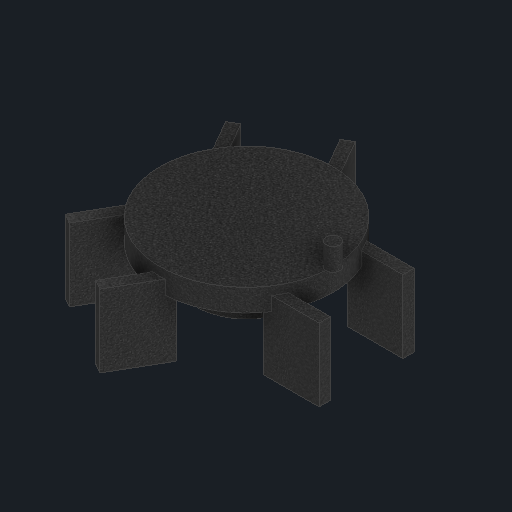
# Autodesk Inventor part: tripod_head
Saved by Autodesk Inventor 2027.1 (Build 311270010, 270A)
## iProperties
Created: 2026-11-03
Part Number: tripod_head
Material: Generic
Description: CG-5 tripod head (estimated)
Document SubType Name: Modeling
Designer: Claude (from photos)
Density: 1 g/cm^3
Appearance: Black Cast
Author: alexg
Autodesk Inventor part; units mm, degrees
ref_plane "YZ Plane" through (0, 0, 0) normal (1, 0, 0) x (0, 1, 0)
sketch "Tripod head plate sketch" plane through (0, 0, 0) normal (0, 1, 0) x (-1, 0, 0)
  circle A0 centre (0, 0) radius 62
  constraints: 1 centre point
extrude "Tripod head plate" add sketch "Tripod head plate sketch" against normal blind 16
ref_plane "Work Plane1" through (0, -16, 0) normal (0, 1, 0) x (-1, 0, 0)
sketch "Centre hub sketch" plane through (0, -16, 0) normal (0, 1, 0) x (-1, 0, 0)
  circle A0 centre (0, 0) radius 36
  constraints: 1 centre point
extrude "Centre hub" add sketch "Centre hub sketch" against normal blind 22
ref_plane "Work Plane2" through (0, -6, 0) normal (0, 1, 0) x (-1, 0, 0)
sketch "Leg hinge ears x3 sketch" plane through (0, -6, 0) normal (0, 1, 0) x (-1, 0, 0)
  line L0 (-46, 26) -> (-86, 26)
  line L1 (-86, 26) -> (-86, 34)
  line L2 (-86, 34) -> (-46, 34)
  line L3 (-46, 34) -> (-46, 26)
  line L4 (-46, -34) -> (-86, -34)
  line L5 (-86, -34) -> (-86, -26)
  line L6 (-86, -26) -> (-46, -26)
  line L7 (-46, -26) -> (-46, -34)
  line L8 (0.4833, -52.8372) -> (20.4833, -87.4782)
  line L9 (20.4833, -87.4782) -> (13.5551, -91.4782)
  line L10 (13.5551, -91.4782) -> (-6.4449, -56.8372)
  line L11 (-6.4449, -56.8372) -> (0.4833, -52.8372)
  line L12 (52.4449, -22.8372) -> (72.4449, -57.4782)
  line L13 (72.4449, -57.4782) -> (65.5167, -61.4782)
  line L14 (65.5167, -61.4782) -> (45.5167, -26.8372)
  line L15 (45.5167, -26.8372) -> (52.4449, -22.8372)
  line L16 (45.5167, 26.8372) -> (65.5167, 61.4782)
  line L17 (65.5167, 61.4782) -> (72.4449, 57.4782)
  line L18 (72.4449, 57.4782) -> (52.4449, 22.8372)
  line L19 (52.4449, 22.8372) -> (45.5167, 26.8372)
  line L20 (-6.4449, 56.8372) -> (13.5551, 91.4782)
  line L21 (13.5551, 91.4782) -> (20.4833, 87.4782)
  line L22 (20.4833, 87.4782) -> (0.4833, 52.8372)
  line L23 (0.4833, 52.8372) -> (-6.4449, 56.8372)
  constraints: 48 end point
extrude "Leg hinge ears x3" add sketch "Leg hinge ears x3 sketch" against normal blind 52
sketch "Azimuth peg sketch" plane through (0, 0, 0) normal (0, 1, 0) x (-1, 0, 0)
  circle A0 centre (-62, 0) radius 5
  constraints: 1 centre point
extrude "Azimuth peg" add sketch "Azimuth peg sketch" along normal blind 16
body "Solid1"
